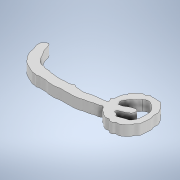
# Autodesk Inventor part: virgula
Saved by Autodesk Inventor 2022.6 (Build 266554000, 554)
## iProperties
Created: 2024-11-29
Part Number: virgula
Material: Generic
Document SubType Name: Modeling
Designer: Dragos Macovei
Density: 1 g/cm^3
Appearance: Default
Author: Dragos Macovei
Autodesk Inventor part; units mm, degrees
ref_plane "YZ Plane" through (0, 0, 0) normal (1, 0, 0) x (0, 1, 0)
ref_plane "XZ Plane" through (0, 0, 0) normal (0, 1, 0) x (-1, 0, 0)
ref_plane "XY Plane" through (0, 0, 0) normal (0, 0, 1) x (1, 0, 0)
sketch "Sketch1" plane through (0, 0, 0) normal (0, 1, 0) x (-1, 0, 0)
  line L0 (0, 0) -> (40, 0)
  line L1 (40, 0) -> (40, 40)
  line L2 (40, 40) -> (0, 40)
  line L3 (0, 40) -> (0, 0)
  line L4 (-150.9907, 198.1907) -> (166.2503, 204.5321) construction
  line L5 (166.2503, 204.5321) -> (174.7055, -218.456) construction
  line L6 (174.7055, -218.456) -> (-142.5355, -224.7974) construction
  line L7 (-142.5355, -224.7974) -> (-150.9907, 198.1907) construction
  spline S0 degree 5 poles (11.7488, 21.915) (11.7908, 21.7939) (11.8395, 21.608) (11.8952, 21.3188) (12.6941, 20.8148) (11.3292, 20.7621) (11.7926, 20.121) (11.5326, 19.5302) (11.3687, 18.8318) (11.4091, 17.8848) (10.0792, 17.7944) (11.3488, 16.9264) (10.3591, 16.6875) (10.0851, 16.031) (9.3425, 16.0966) (8.8995, 14.3573) (7.9384, 15.825) (7.0636, 13.8072) (6.7817, 14.9147) (5.797, 14.3432) (5.2413, 14.655) (4.0568, 14.5883) (3.6722, 14.5233) (3.1623, 15.5167) (2.6293, 15.8623) (2.2752, 16.2317) (1.4243, 17.7272) (1.4241, 17.8505) (1.7862, 19.5691) (0.884, 19.6859) (1.3741, 20.8055) (1.1506, 21.3728) (1.5307, 22.7659) (1.1928, 23.3748) (2.498, 23.8727) (2.3049, 24.7368) (3.2693, 25.6347) (3.9267, 25.7927) (4.5055, 26.6637) (5.5301, 25.896) (5.6642, 26.899) (6.2843, 26.872) (6.925, 26.9884) (7.0449, 26.1784) (7.4959, 26.5534) (8.4758, 26.7348) (8.5846, 26.099) (9.3234, 26.3094) (9.354, 25.8163) (9.7629, 25.3892) (9.9891, 25.527) (10.6336, 24.996) (10.819, 24.8983) (10.7623, 24.0337) (11.9724, 24.3966) (11.2216, 22.9358) (11.5642, 22.3666) (11.6918, 22.0793) (11.7488, 21.915) knots 0 0 0 0 0 0 0.019584 0.032363 0.048714 0.065889 0.084006 0.102203 0.120814 0.138977 0.156732 0.17402 0.192542 0.211842 0.23256 0.252573 0.272648 0.292201 0.312049 0.33048 0.34996 0.369247 0.388122 0.40774 0.427982 0.449022 0.47002 0.491193 0.511304 0.532616 0.552768 0.573494 0.594571 0.616174 0.636998 0.658151 0.678935 0.698932 0.717604 0.735281 0.751864 0.767536 0.783911 0.800145 0.816197 0.832204 0.848252 0.862692 0.8774 0.891814 0.906437 0.921524 0.939092 0.957608 0.973423 1 1 1 1 1 1
  spline S1 degree 4 poles (9.3376, 21.3394) (9.0186, 21.2894) (8.4499, 21.3867) (7.5562, 20.4472) (6.6391, 20.206) (5.6319, 19.8015) (4.979, 20.2993) (5.0846, 20.9383) (5.246, 21.714) (5.6685, 21.8551) (6.3549, 22.4692) (6.862, 22.4916) (7.3955, 22.8857) (7.8398, 22.9271) (8.3048, 23.2321) (8.2749, 23.3814) (8.3584, 23.9325) (7.7937, 23.9511) (7.2895, 24.0782) (7.1942, 24.4428) (7.0799, 24.6252) (6.7993, 24.8062) (6.1615, 24.4505) (5.6385, 24.3726) (5.2477, 24.1139) (4.3986, 23.9103) (4.2114, 23.6697) (3.5313, 23.6954) (3.7596, 22.9387) (4.0559, 23.0417) (3.2926, 22.7295) (3.2145, 22.5981) (3.0779, 22.3481) (3.0048, 22.2203) knots 0 0 0 0 0 0.091303 0.133055 0.173893 0.212329 0.249456 0.283357 0.318734 0.353889 0.388619 0.423632 0.455523 0.483706 0.510023 0.536136 0.563431 0.592031 0.618724 0.643002 0.668032 0.69566 0.726672 0.761993 0.795621 0.828015 0.859887 0.884832 0.909511 0.933992 0.957783 1 1 1 1 1
  spline S2 degree 4 poles (7.1748, 16.5833) (7.2179, 16.6022) (7.3242, 16.6847) (7.446, 16.9853) (7.786, 17.3128) (8.074, 17.4494) (8.2068, 17.783) (8.6636, 18.1206) (8.8566, 18.2176) (9.1616, 18.5081) (9.3124, 18.9979) (9.495, 19.096) (9.7955, 19.4486) (9.8325, 19.7567) (10.0516, 20.2468) (10.0611, 20.4291) (9.8275, 21.0259) (9.5845, 20.8875) (9.7345, 21.6329) (9.3376, 21.3394) knots 0.378285 0.378285 0.378285 0.378285 0.378285 0.400113 0.438651 0.477232 0.516838 0.553264 0.590805 0.629628 0.66517 0.702037 0.738781 0.77568 0.812703 0.849641 0.884022 0.916632 1 1 1 1 1
  spline S3 degree 4 poles (4.454, 23.8682) (3.9011, 24.026) (2.9003, 22.5837) (2.8213, 21.5011) (2.72, 19.1557) (3.1432, 17.4454) (5.0625, 16.4049) (5.8095, 15.5089) (7.1748, 16.5833) knots 0 0 0 0 0 0.288554 0.414789 0.541255 0.668871 1 1 1 1 1
  line L8 (6.418, 16.2511) -> (7.9315, 16.9155) construction
  arc A0 (6.8969, 16.6372) -> (7.3232, 16.8244) centre (7.0748, 16.811) ccw construction
  line L9 (3.7066, 23.4479) -> (2.303, 20.9927) construction
  arc A1 (2.3663, 21.3026) -> (3.4716, 23.2361) centre (-2.4815, 25.3567) ccw construction
  spline S4 degree 4 poles (11.3285, 24.1299) (11.7886, 23.872) (11.9686, 24.6813) (12.8462, 24.3287) (13.9849, 24.8316) (14.8064, 25.1459) (15.9791, 25.1492) (16.5539, 25.5748) (17.4084, 25.65) (18.2486, 25.8656) (19.0101, 25.8014) (19.8697, 25.77) (20.9298, 25.9635) (21.7172, 25.7014) (23.0043, 25.9744) (23.9499, 26.2445) (24.6496, 25.9729) (25.629, 26.1563) (25.9476, 25.8739) (26.9094, 25.7577) (27.7906, 25.9004) (28.3247, 25.6239) (29.2798, 26.1873) (29.24, 25.7487) (30.4835, 25.9068) (31.0181, 25.5097) (32.1002, 25.0489) (32.4582, 24.8738) (33.6817, 24.1821) (33.9363, 24.0127) (34.8002, 22.8531) (35.1348, 22.721) (35.8057, 21.3067) (36.0294, 20.7534) (36.1949, 19.2603) (36.6971, 18.7327) (36.8608, 17.1435) (36.3506, 16.7318) (35.2129, 15.7354) (34.8503, 16.6753) (34.5423, 17.3068) (34.3845, 18.3848) (33.8189, 19.2496) (33.0427, 20.2786) (32.8079, 21.1747) (32.1392, 21.7661) (31.7418, 22.1887) (30.8193, 22.7163) (30.4165, 22.406) (29.7422, 22.9149) (28.9547, 23.0721) (28.2876, 22.8124) (27.4161, 23.405) (27.1717, 23.1017) (25.7683, 23.5076) (25.5593, 23.4087) (24.2676, 23.5145) (23.5291, 23.2829) (22.514, 23.3057) (21.8863, 23.4582) (20.7804, 22.4551) (20.3519, 23.4177) (19.5272, 23.1212) (18.6624, 23.4231) (16.5513, 23.3969) (15.8924, 22.2956) (11.708, 22.7872) (11.7485, 21.9157) knots 0 0 0 0 0 0.030737 0.044929 0.060388 0.075833 0.090937 0.105711 0.119799 0.134203 0.14904 0.164007 0.180041 0.196337 0.212169 0.227718 0.241437 0.254913 0.268731 0.282388 0.296621 0.309035 0.321289 0.334037 0.347499 0.362275 0.377542 0.39205 0.406745 0.421392 0.436266 0.451837 0.467651 0.484187 0.500764 0.5173 0.533409 0.548754 0.563115 0.577703 0.592577 0.608888 0.625582 0.64179 0.657053 0.671437 0.684602 0.697563 0.710795 0.723815 0.737667 0.750884 0.764708 0.777953 0.791796 0.806873 0.821504 0.836729 0.851964 0.866517 0.880521 0.894781 0.909337 0.925116 0.944423 1 1 1 1 1
  point P0 (12.1868, 20.9569)
  point P1 (11.7488, 20.6558)
  point P2 (11.6282, 20.2313)
  point P3 (11.576, 19.6004)
  point P4 (11.4072, 18.7887)
  point P5 (11.0255, 18.0012)
  point P6 (10.6518, 17.5873)
  point P7 (10.8567, 17.0529)
  point P8 (10.5753, 16.6585)
  point P9 (10.0567, 16.2321)
  point P10 (9.5034, 15.8171)
  point P11 (8.7772, 15.0679)
  point P12 (7.9128, 15.0448)
  point P13 (7.0829, 14.4455)
  point P14 (6.6564, 14.5492)
  point P15 (5.9418, 14.5377)
  point P16 (5.1234, 14.5723)
  point P17 (4.1321, 14.5953)
  point P18 (3.6711, 14.7452)
  point P19 (3.1639, 15.3676)
  point P20 (2.7144, 15.8286)
  point P21 (2.2764, 16.3243)
  point P22 (1.5963, 17.4884)
  point P23 (1.5041, 18.18)
  point P24 (1.4696, 19.3326)
  point P25 (1.1929, 19.8974)
  point P26 (1.216, 20.6236)
  point P27 (1.2736, 21.4765)
  point P28 (1.3889, 22.6868)
  point P29 (1.5502, 23.3323)
  point P30 (2.1496, 23.9316)
  point P31 (2.5415, 24.7039)
  point P32 (3.2677, 25.5107)
  point P33 (3.9823, 25.9948)
  point P34 (4.7085, 26.3061)
  point P35 (5.4116, 26.3176)
  point P36 (5.815, 26.721)
  point P37 (6.3452, 26.8939)
  point P38 (6.8293, 26.7671)
  point P39 (7.1059, 26.4559)
  point P40 (7.5093, 26.4789)
  point P41 (8.3392, 26.5251)
  point P42 (8.7772, 26.2599)
  point P43 (9.2037, 26.1332)
  point P44 (9.4458, 25.8104)
  point P45 (9.7339, 25.5107)
  point P46 (10.0221, 25.407)
  point P47 (10.5292, 25.0843)
  point P48 (10.7482, 24.7961)
  point P49 (10.9327, 24.3696)
  point P50 (11.4052, 24.0699)
  point P51 (11.4744, 22.8482)
  point P52 (8.1867, 21.026)
  point P53 (7.3497, 20.4857)
  point P54 (6.5475, 20.1546)
  point P55 (5.5883, 20.0013)
  point P56 (5.1174, 20.364)
  point P57 (5.0999, 20.9743)
  point P58 (5.3091, 21.6019)
  point P59 (5.6753, 21.9157)
  point P60 (6.3554, 22.3691)
  point P61 (6.8961, 22.5783)
  point P62 (7.4367, 22.8398)
  point P63 (7.925, 23.0142)
  point P64 (8.239, 23.2408)
  point P65 (8.2913, 23.4152)
  point P66 (8.2564, 23.7814)
  point P67 (7.8029, 23.9732)
  point P68 (7.3145, 24.1825)
  point P69 (7.175, 24.4441)
  point P70 (7.0703, 24.6011)
  point P71 (6.861, 24.7057)
  point P72 (6.2505, 24.5312)
  point P73 (5.6749, 24.3393)
  point P74 (5.1691, 24.1299)
  point P75 (4.0702, 23.7112)
  point P76 (3.6865, 23.4844)
  point P77 (3.8434, 23.0308)
  point P78 (3.8879, 22.9888)
  point P79 (3.5433, 22.8189)
  point P80 (3.2084, 22.5616)
  point P81 (7.8027, 17.2934)
  point P82 (8.0423, 17.4884)
  point P83 (8.2564, 17.7672)
  point P84 (8.6412, 18.0928)
  point P85 (8.867, 18.248)
  point P86 (9.1286, 18.5443)
  point P87 (9.3381, 18.9516)
  point P88 (9.5039, 19.1326)
  point P89 (9.7344, 19.4249)
  point P90 (9.8665, 19.7868)
  point P91 (10.0224, 20.2321)
  point P92 (10.0222, 20.4856)
  point P93 (9.8662, 20.8162)
  point P94 (9.7339, 20.9736)
  point P95 (9.6432, 21.2869)
  point P96 (3.6865, 23.4845)
  point P97 (2.8016, 20.8739)
  point P98 (2.8058, 19.199)
  point P99 (3.1893, 18.0014)
  point P100 (4.1986, 16.9499)
  point P101 (5.4235, 16.1464)
  point P102 (3.0048, 22.2203)
  point P103 (11.8327, 24.1824)
  point P104 (12.285, 24.4438)
  point P105 (13.0041, 24.5308)
  point P106 (13.9203, 24.7956)
  point P107 (14.883, 25.0837)
  point P108 (15.9501, 25.2581)
  point P109 (16.6229, 25.5101)
  point P110 (17.4, 25.6756)
  point P111 (18.2351, 25.8098)
  point P112 (18.9891, 25.8099)
  point P113 (19.8475, 25.81)
  point P114 (20.8451, 25.8731)
  point P115 (21.7498, 25.8102)
  point P116 (23.0258, 25.9947)
  point P117 (24.0001, 26.1331)
  point P118 (24.7773, 26.059)
  point P119 (25.5545, 26.059)
  point P120 (25.9952, 25.9314)
  point P121 (26.8536, 25.8105)
  point P122 (27.7931, 25.8105)
  point P123 (28.5006, 25.8104)
  point P124 (29.1502, 25.9948)
  point P125 (29.3589, 25.9082)
  point P126 (30.2173, 25.8104)
  point P127 (31.0988, 25.5107)
  point P128 (32.0035, 25.0842)
  point P129 (32.5835, 24.796)
  point P130 (33.5462, 24.2495)
  point P131 (34.0101, 23.8681)
  point P132 (34.7177, 23.0308)
  point P133 (35.1353, 22.5616)
  point P134 (35.7152, 21.4765)
  point P135 (36.0052, 20.6236)
  point P136 (36.272, 19.4249)
  point P137 (36.62, 18.5443)
  point P138 (36.7012, 17.2934)
  point P139 (36.1792, 16.5833)
  point P140 (35.2861, 16.1268)
  point P141 (34.8801, 16.5833)
  point P142 (34.6017, 17.2934)
  point P143 (34.3349, 18.248)
  point P144 (33.7897, 19.2619)
  point P145 (33.0938, 20.3639)
  point P146 (32.6646, 21.1989)
  point P147 (32.1542, 21.7672)
  point P148 (31.6207, 22.2201)
  point P149 (30.8436, 22.5615)
  point P150 (30.4028, 22.5615)
  point P151 (29.7765, 22.8188)
  point P152 (28.9762, 22.9887)
  point P153 (28.2222, 22.9887)
  point P154 (27.5031, 23.2361)
  point P155 (27.0623, 23.2361)
  point P156 (25.9604, 23.4152)
  point P157 (25.4385, 23.4479)
  point P158 (24.3945, 23.4478)
  point P159 (23.455, 23.3322)
  point P160 (22.5619, 23.3322)
  point P161 (21.8079, 23.236)
  point P162 (20.8336, 22.8481)
  point P163 (20.2768, 23.1707)
  point P164 (19.6273, 23.2359)
  point P165 (18.7573, 23.3321)
  point P166 (17.551, 23.3321)
  point P167 (16.3716, 22.9887)
  point P168 (13.5434, 22.5615)
  point P169 (3.8538, 23.6512)
  dimension "d0" = 40
  dimension "d1" = 40
  constraints: 12 end point, 4 midpoint, 2 centre point, 2 parallel, 2 point on circle, 1 horizontal, 1 perpendicular, 193 other
  measures "d0" distance of L2.end L1.end
  measures "d1" distance of L1.end L0.end
extrude "Extrusion1" add sketch "Sketch1" along normal blind 3 contours S0 | S0 S4
body "Solid1"
